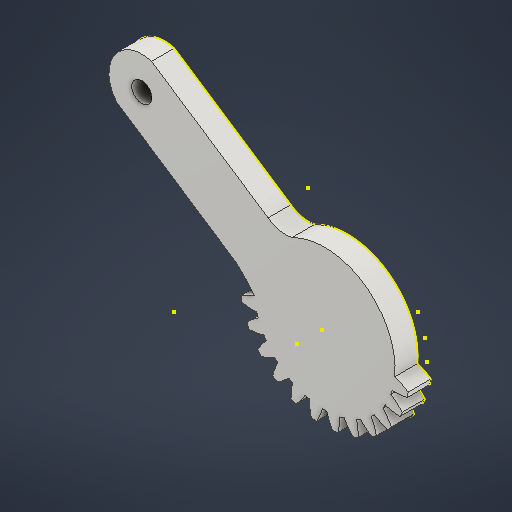
# Autodesk Inventor part: Przekładnia walcowa1
Saved by Autodesk Inventor 2026.1 (Build 301233020, 233B)
## iProperties
CustomPartVersion: 1
Created: 2026-01-25
Part Number: Przekładnia walcowa1
Material: Steel
Document SubType Name: Modeling
Designer: Nitro
Categories: <?xml version="1.0" encoding="UTF-16"?> <MemberInstance><Categories><FamilyTemplate><FamilyTemplateParameter ValueType="xs:double" Id="1" ObjectReferenceKey="da_z" ObjectType="kUserParameterObject"/><FamilyTemplateParameter ValueType="xs:double" Id="2" ObjectReferenceKey="da_b" ObjectType="kUserParameterObject"/><FamilyTemplateParameter ValueType="xs:double" Id="3" ObjectReferenceKey="da_beta" ObjectType="kUserParameterObject"/><FamilyTemplateParameter ValueType="xs:double" Id="4" ObjectReferenceKey="da_da" ObjectType="kUserParameterObject"/><FamilyTemplateParameter ValueType="xs:double" Id="5" ObjectReferenceKey="da_aw" ObjectType="kUserParameterObject"/><FamilyTemplateParameter ValueType="xs:string" Id="6" ObjectReferenceKey="EAIAABAAAACIAQAAAAAAAIAAAAAAAAAA" ObjectType="83910656" SubObjectId="SurfaceGeometry"/></FamilyTemplate><ParamToTemplateMap><ParamToTemplate CategoryParameter="//CategoryParameter[@InternalName='046C89C9-8512-4d59-83FE-43B91F4F132A']" TemplateParameter="1"/><ParamToTemplate CategoryParameter="//CategoryParameter[@InternalName='2552DF32-E462-4b46-AEBF-C6C7768E72AC']" TemplateParameter="2"/><ParamToTemplate CategoryParameter="//CategoryParameter[@InternalName='C9EE641D-15FC-4fae-A226-E94C4372FDD7']" TemplateParameter="3"/><ParamToTemplate><ParamToTemplate CategoryParameter="//CategoryParameter[@InternalName='00B6519A-459B-49c7-AD84-2E56D39A5744']" ConstantValue="0.000000"/></ParamToTemplate><ParamToTemplate><ParamToTemplate CategoryParameter="//CategoryParameter[@InternalName='04B31F0E-C7A6-4894-AA32-9629BEFACF47']" ConstantValue="1.000000"/></ParamToTemplate><ParamToTemplate><ParamToTemplate CategoryParameter="//CategoryParameter[@InternalName='43CBEC2E-7847-49e7-A936-2F7889FCB2D9']" ConstantValue="0.250000"/></ParamToTemplate><ParamToTemplate><ParamToTemplate CategoryParameter="//CategoryParameter[@InternalName='B1EFC894-105D-4ebd-86BF-FA20ED196853']" ConstantValue="0.350000"/></ParamToTemplate><ParamToTemplate><ParamToTemplate CategoryParameter="//CategoryParameter[@InternalName='51175063-3D10-4879-93E8-6246FE8B403D']" ConstantValue="2060000000.000000"/></ParamToTemplate><ParamToTemplate><ParamToTemplate CategoryParameter="//CategoryParameter[@InternalName='A3A52E27-4454-46a9-B0BD-C932399B70AF']" ConstantValue="0.300000"/></ParamToTemplate><ParamToTemplate><ParamToTemplate CategoryParameter="//CategoryParameter[@InternalName='91B76062-C214-41d9-B1B9-14D2AB99603D']" ConstantValue="0.125000"/></ParamToTemplate><ParamToTemplate><ParamToTemplate CategoryParameter="//CategoryParameter[@InternalName='374E806E-8B8A-4dda-A9AA-1039D6500AD2']" ConstantValue="8.000000"/></ParamToTemplate><ParamToTemplate><ParamToTemplate CategoryParameter="//CategoryParameter[@InternalName='2D373A89-B862-43d6-8D0B-0CBF12AB9F6C']" ConstantValue="0.349066"/></ParamToTemplate><ParamToTemplate CategoryParameter="//CategoryParameter[@InternalName='37777632-D6A2-4fac-9D53-DB8ACD95C989']" TemplateParameter="4"/><ParamToTemplate CategoryParameter="//CategoryParameter[@InternalName='FD1017F1-B727-4f7e-9707-0F86F1FF9423']" TemplateParameter="5"/><ParamToTemplate><ParamToTemplate CategoryParameter="//CategoryParameter[@InternalName='9E1B4470-B2D3-4ff1-B813-535BB4CDF51A']" ConstantValue="3520000.000000"/></ParamToTemplate><ParamToTemplate><ParamToTemplate CategoryParameter="//CategoryParameter[@InternalName='F8452263-BFF6-458c-9FB1-07C4B99E95CD']" ConstantValue="11400000.000000"/></ParamToTemplate><ParamToTemplate><ParamToTemplate CategoryParameter="//CategoryParameter[@InternalName='3E3BB259-FD49-497f-8171-6EBC954A3479']" ConstantValue="2.000000"/></ParamToTemplate><ParamToTemplate CategoryParameter="//CategoryParameter[@InternalName='27C3BAF2-7550-4e4b-AE2C-0DB134B7D9B7']" TemplateParameter="6"/></ParamToTemplateMap><Category DisplayName="Gear" InternalName="DC85795E-93AB-48d5-8EEE-5A27447B64BD" Mnemonic="Gear"><CategoryParameter DisplayName="z" InternalName="046C89C9-8512-4d59-83FE-43B91F4F132A" Mnemonic="z"/><CategoryParameter DisplayName="b" InternalName="2552DF32-E462-4b46-AEBF-C6C7768E72AC" Mnemonic="b"/><CategoryParameter DisplayName="||b|" InternalName="C9EE641D-15FC-4fae-A226-E94C4372FDD7" Mnemonic="beta"/><CategoryParameter DisplayName="x" InternalName="00B6519A-459B-49c7-AD84-2E56D39A5744" Mnemonic="x"/><CategoryParameter DisplayName="a*" InternalName="04B31F0E-C7A6-4894-AA32-9629BEFACF47" Mnemonic="a"/><CategoryParameter DisplayName="c*" InternalName="43CBEC2E-7847-49e7-A936-2F7889FCB2D9" Mnemonic="c"/><CategoryParameter DisplayName="r|.f|*" InternalName="B1EFC894-105D-4ebd-86BF-FA20ED196853" Mnemonic="rf"/><CategoryParameter DisplayName="E" InternalName="51175063-3D10-4879-93E8-6246FE8B403D" Mnemonic="E"/><CategoryParameter DisplayName="||m|" InternalName="A3A52E27-4454-46a9-B0BD-C932399B70AF" Mnemonic="mi"/><Category DisplayName="SpurGear" InternalName="26C5A22E-A91E-4dfd-A3B3-23CCAFAE1764" Mnemonic="SpurGear"><CategoryParameter DisplayName="m" InternalName="91B76062-C214-41d9-B1B9-14D2AB99603D" Mnemonic="m"/><CategoryParameter DisplayName="P" InternalName="374E806E-8B8A-4dda-A9AA-1039D6500AD2" Mnemonic="PP"/><CategoryParameter DisplayName="||a|" InternalName="2D373A89-B862-43d6-8D0B-0CBF12AB9F6C" Mnemonic="alpha"/><CategoryParameter DisplayName="d|.a|" InternalName="37777632-D6A2-4fac-9D53-DB8ACD95C989" Mnemonic="da"/><CategoryParameter DisplayName="a|.w|" InternalName="FD1017F1-B727-4f7e-9707-0F86F1FF9423" Mnemonic="aw"/><CategoryParameter DisplayName="||s||.Flim|" InternalName="9E1B4470-B2D3-4ff1-B813-535BB4CDF51A" Mnemonic="sFlim"/><CategoryParameter DisplayName="||s||.Hlim|" InternalName="F8452263-BFF6-458c-9FB1-07C4B99E95CD" Mnemonic="sHlim"/><CategoryParameter DisplayName="typ" InternalName="3E3BB259-FD49-497f-8171-6EBC954A3479" Mnemonic="type"/><CategoryParameter DisplayName="PitchDiameter" InternalName="27C3BAF2-7550-4e4b-AE2C-0DB134B7D9B7" Mnemonic="IDS_PITCHDIAM"/></Category></Category></Categories></MemberInstance>
Density: 1 g/cm^3
Appearance: Steel
d16: 109,375 mm
d17: 0,000 mm
d41: 0,000 mm
d43: 109,375 mm
d46: 109,375 mm
d47: 0,000 mm
d48: 0,000 mm
Author: Nitro
Autodesk Inventor part; units mm, degrees
ref_plane "YZ Plane" through (0, 0, 0) normal (1, 0, 0) x (0, 1, 0)
ref_plane "XZ Plane" through (0, 0, 0) normal (0, 1, 0) x (-1, 0, 0)
ref_plane "XY Plane" through (0, 0, 0) normal (0, 0, 1) x (1, 0, 0)
sketch "Sketch1" plane through (0, 0, 0) normal (0, 0, 1) x (1, 0, 0)
  circle A0 centre (0, 0) radius 16.875
  dimension "d0" = 33.75
  constraints: 1 centre point
  measures "d0" diameter of A0
extrude "Extrusion1" add sketch "Sketch1" along normal blind 10
ref_plane "Work Plane2" through (0, 0, 5) normal (0, 0, 1) x (1, 0, 0)
sketch "Sketch2" plane through (0, 0, 0) normal (0, 0, -1) x (-1, 0, 0)
  circle A0 centre (0, 0) radius 16.875 projected
  circle A1 centre (0, 0) radius 15.625
  dimension "d3" = 31.25
  constraints: 1 centre point, 1 coincident
  measures "d3" diameter of A1
surface extrude "Średnica podziałowa" sketch "Sketch2" against normal through all shown no curves A1
ref_plane "Work Plane8" through (0, 0, 0) normal (0.9921147, 0.1253332, 0) x (0, 0, 1)
ref_plane "Work Plane9" through (0, 0, 0) normal (1, 0, 0) x (0, 1, 0)
spur gear teeth "Przekładnia walcowa" teeth 25 pitch diameter 31.25 tip diameter 33.75 root diameter 28.125 face width 10 start plane through (0, 0, 0) normal (0, 0, -1) x (-1, 0, 0)
sketch "Szkic3" plane through (0, 0, 10) normal (0, 0, 1) x (1, 0, 0)
  point P0 (0, 0)
sketch "Szkic4" plane through (0, 0, 10) normal (0, 0, 1) x (1, 0, 0)
  circle A0 centre (0, 0) radius 14.0625
  circle A1 centre (0, 0) radius 17.845892
  line L0 (-14.033168, -0.907808) -> (-17.792827, -1.375198)
  line L1 (14.055561, -0.907808) -> (17.792827, -1.375198)
  arc A2 (-4.707975, 16.204956) -> (-4.763502, 13.231136) centre (6.715955, 14.50422) ccw
  arc A3 (-4.763502, 13.231136) -> (-5.584892, 12.905924) centre (0, 0) ccw
  arc A4 (-5.584892, 12.905924) -> (-7.66109, 15.035735) centre (-14.824542, 5.975734) ccw
  arc A5 (-7.66109, 15.035735) -> (-8.590074, 14.525022) centre (0, 0) ccw
  arc A6 (-8.590074, 14.525022) -> (-7.904298, 11.630821) centre (2.897908, 15.718734) ccw
  arc A7 (-7.904298, 11.630821) -> (-8.619005, 11.111555) centre (0, 0) ccw
  arc A8 (-8.619005, 11.111555) -> (-11.159638, 12.658124) centre (-15.844907, 2.101281) ccw
  arc A9 (-11.159638, 12.658124) -> (-11.932427, 11.932427) centre (0, 0) ccw
  arc A10 (-11.932427, 11.932427) -> (-10.548437, 9.299698) centre (-1.102225, 15.945581) ccw
  arc A11 (-10.548437, 9.299698) -> (-11.111555, 8.619005) centre (0, 0) ccw
  arc A12 (-11.111555, 8.619005) -> (-13.956985, 9.485157) centre (-15.869677, -1.905202) ccw
  arc A13 (-13.956985, 9.485157) -> (-14.525022, 8.590074) centre (0, 0) ccw
  arc A14 (-14.525022, 8.590074) -> (-12.529779, 6.384241) centre (-5.033101, 15.170509) ccw
  arc A15 (-12.529779, 6.384241) -> (-12.905924, 5.584892) centre (0, 0) ccw
  arc A16 (-12.905924, 5.584892) -> (-15.877363, 5.716202) centre (-14.897298, -5.791975) ccw
  arc A17 (-15.877363, 5.716202) -> (-16.204956, 4.707975) centre (0, 0) ccw
  arc A18 (-16.204956, 4.707975) -> (-13.723829, 3.067639) centre (-8.647729, 13.442218) ccw
  arc A19 (-13.723829, 3.067639) -> (-13.889367, 2.19986) centre (0, 0) ccw
  arc A20 (-13.889367, 2.19986) -> (-16.800108, 1.588078) centre (-12.988866, -9.314817) ccw
  arc A21 (-16.800108, 1.588078) -> (-16.866673, 0.530057) centre (0, 0) ccw
  arc A22 (-16.866673, 0.530057) -> (-14.055561, -0.441714) centre (-11.718989, 10.869303) ccw
  arc A23 (-14.055561, -0.441714) -> (-14.00009, -1.323398) centre (0, 0) ccw
  arc A24 (-14.00009, -1.323398) -> (-16.667241, -2.639832) centre (-10.264296, -12.252374) ccw
  arc A25 (-16.667241, -2.639832) -> (-16.468595, -3.681167) centre (0, 0) ccw
  arc A26 (-16.468595, -3.681167) -> (-13.50413, -3.923312) centre (-14.053901, 7.61343) ccw
  arc A27 (-13.50413, -3.923312) -> (-13.231136, -4.763502) centre (0, 0) ccw
  arc A28 (-13.231136, -4.763502) -> (-15.487109, -6.701871) centre (-6.894783, -14.42007) ccw
  arc A29 (-15.487109, -6.701871) -> (-15.035735, -7.66109) centre (0, 0) ccw
  arc A30 (-15.035735, -7.66109) -> (-12.104185, -7.158395) centre (-15.505755, 3.879177) ccw
  arc A31 (-12.104185, -7.158395) -> (-11.630821, -7.904298) centre (0, 0) ccw
  arc A32 (-11.630821, -7.904298) -> (-13.333866, -10.342807) centre (-3.092045, -15.6817) ccw
  arc A33 (-13.333866, -10.342807) -> (-12.658124, -11.159638) centre (0, 0) ccw
  arc A34 (-12.658124, -11.159638) -> (-9.943689, -9.943689) centre (-15.983325, -0.098819) ccw
  arc A35 (-9.943689, -9.943689) -> (-9.299698, -10.548437) centre (0, 0) ccw
  arc A36 (-9.299698, -10.548437) -> (-10.342807, -13.333866) centre (0.904978, -15.957991) ccw
  arc A37 (-10.342807, -13.333866) -> (-9.485157, -13.956985) centre (0, 0) ccw
  arc A38 (-9.485157, -13.956985) -> (-7.158395, -12.104185) centre (-15.456605, -4.070606) ccw
  arc A39 (-7.158395, -12.104185) -> (-6.384241, -12.529779) centre (0, 0) ccw
  arc A40 (-6.384241, -12.529779) -> (-6.701871, -15.487109) centre (4.845137, -15.231582) ccw
  arc A41 (-6.701871, -15.487109) -> (-5.716202, -15.877363) centre (0, 0) ccw
  arc A42 (-5.716202, -15.877363) -> (-3.923312, -13.50413) centre (-13.958688, -7.786621) ccw
  arc A43 (-3.923312, -13.50413) -> (-3.067639, -13.723829) centre (0, 0) ccw
  arc A44 (-3.067639, -13.723829) -> (-2.639832, -16.667241) centre (8.480859, -13.548118) ccw
  arc A45 (-2.639832, -16.667241) -> (-1.588078, -16.800108) centre (0, 0) ccw
  arc A46 (-1.588078, -16.800108) -> (-0.441714, -14.055561) centre (-11.583697, -11.013375) ccw
  arc A47 (-0.441714, -14.055561) -> (0.441714, -14.055561) centre (0, 0) ccw
  arc A48 (0.441714, -14.055561) -> (1.588078, -16.800108) centre (11.583697, -11.013375) ccw
  arc A49 (1.588078, -16.800108) -> (2.639832, -16.667241) centre (0, 0) ccw
  arc A50 (2.639832, -16.667241) -> (3.067639, -13.723829) centre (-8.480859, -13.548118) ccw
  arc A51 (3.067639, -13.723829) -> (3.923312, -13.50413) centre (0, 0) ccw
  arc A52 (3.923312, -13.50413) -> (5.716202, -15.877363) centre (13.958688, -7.786621) ccw
  arc A53 (5.716202, -15.877363) -> (6.701871, -15.487109) centre (0, 0) ccw
  arc A54 (6.701871, -15.487109) -> (6.384241, -12.529779) centre (-4.845137, -15.231582) ccw
  arc A55 (6.384241, -12.529779) -> (7.158395, -12.104185) centre (0, 0) ccw
  arc A56 (7.158395, -12.104185) -> (9.485157, -13.956985) centre (15.456605, -4.070606) ccw
  arc A57 (9.485157, -13.956985) -> (10.342807, -13.333866) centre (0, 0) ccw
  arc A58 (10.342807, -13.333866) -> (9.299698, -10.548437) centre (-0.904978, -15.957991) ccw
  arc A59 (9.299698, -10.548437) -> (9.943689, -9.943689) centre (0, 0) ccw
  arc A60 (9.943689, -9.943689) -> (12.658124, -11.159638) centre (15.983325, -0.098819) ccw
  arc A61 (12.658124, -11.159638) -> (13.333866, -10.342807) centre (0, 0) ccw
  arc A62 (13.333866, -10.342807) -> (11.630821, -7.904298) centre (3.092045, -15.6817) ccw
  arc A63 (11.630821, -7.904298) -> (12.104185, -7.158395) centre (0, 0) ccw
  arc A64 (12.104185, -7.158395) -> (15.035735, -7.66109) centre (15.505755, 3.879177) ccw
  arc A65 (15.035735, -7.66109) -> (15.487109, -6.701871) centre (0, 0) ccw
  arc A66 (15.487109, -6.701871) -> (13.231136, -4.763502) centre (6.894783, -14.42007) ccw
  arc A67 (13.231136, -4.763502) -> (13.50413, -3.923312) centre (0, 0) ccw
  arc A68 (13.50413, -3.923312) -> (16.468595, -3.681167) centre (14.053901, 7.61343) ccw
  arc A69 (16.468595, -3.681167) -> (16.667241, -2.639832) centre (0, 0) ccw
  arc A70 (16.667241, -2.639832) -> (14.00009, -1.323398) centre (10.264296, -12.252374) ccw
  arc A71 (14.00009, -1.323398) -> (14.055561, -0.441714) centre (0, 0) ccw
  arc A72 (14.055561, -0.441714) -> (16.866673, 0.530057) centre (11.718989, 10.869303) ccw
  arc A73 (16.866673, 0.530057) -> (16.800108, 1.588078) centre (0, 0) ccw
  arc A74 (16.800108, 1.588078) -> (13.889367, 2.19986) centre (12.988866, -9.314817) ccw
  arc A75 (13.889367, 2.19986) -> (13.723829, 3.067639) centre (0, 0) ccw
  arc A76 (13.723829, 3.067639) -> (16.204956, 4.707975) centre (8.647729, 13.442218) ccw
  arc A77 (16.204956, 4.707975) -> (15.877363, 5.716202) centre (0, 0) ccw
  arc A78 (15.877363, 5.716202) -> (12.905924, 5.584892) centre (14.897298, -5.791975) ccw
  arc A79 (12.905924, 5.584892) -> (12.529779, 6.384241) centre (0, 0) ccw
  arc A80 (12.529779, 6.384241) -> (14.525022, 8.590074) centre (5.033101, 15.170509) ccw
  arc A81 (14.525022, 8.590074) -> (13.956985, 9.485157) centre (0, 0) ccw
  arc A82 (13.956985, 9.485157) -> (11.111555, 8.619005) centre (15.869677, -1.905202) ccw
  arc A83 (11.111555, 8.619005) -> (10.548437, 9.299698) centre (0, 0) ccw
  arc A84 (10.548437, 9.299698) -> (11.932427, 11.932427) centre (1.102225, 15.945581) ccw
  arc A85 (11.932427, 11.932427) -> (11.159638, 12.658124) centre (0, 0) ccw
  arc A86 (11.159638, 12.658124) -> (8.619005, 11.111555) centre (15.844907, 2.101281) ccw
  arc A87 (8.619005, 11.111555) -> (7.904298, 11.630821) centre (0, 0) ccw
  arc A88 (7.904298, 11.630821) -> (8.590074, 14.525022) centre (-2.897908, 15.718734) ccw
  arc A89 (8.590074, 14.525022) -> (7.66109, 15.035735) centre (0, 0) ccw
  arc A90 (7.66109, 15.035735) -> (5.584892, 12.905924) centre (14.824542, 5.975734) ccw
  arc A91 (5.584892, 12.905924) -> (4.763502, 13.231136) centre (0, 0) ccw
  arc A92 (4.763502, 13.231136) -> (4.707975, 16.204956) centre (-6.715955, 14.50422) ccw
  arc A93 (4.707975, 16.204956) -> (3.681167, 16.468595) centre (0, 0) ccw
  arc A94 (3.681167, 16.468595) -> (2.19986, 13.889367) centre (12.872698, 9.474709) ccw
  arc A95 (2.19986, 13.889367) -> (1.323398, 14.00009) centre (0, 0) ccw
  arc A96 (1.323398, 14.00009) -> (0.530057, 16.866673) centre (-10.112014, 12.378353) ccw
  arc A97 (0.530057, 16.866673) -> (-0.530057, 16.866673) centre (0, 0) ccw
  arc A98 (-0.530057, 16.866673) -> (-1.323398, 14.00009) centre (10.112014, 12.378353) ccw
  arc A99 (-1.323398, 14.00009) -> (-2.19986, 13.889367) centre (0, 0) ccw
  arc A100 (-2.19986, 13.889367) -> (-3.681167, 16.468595) centre (-12.872698, 9.474709) ccw
  arc A101 (-3.681167, 16.468595) -> (-4.707975, 16.204956) centre (0, 0) ccw
  point P0 (14.00009, -1.323398)
  point P1 (13.50413, -3.923312)
  point P2 (13.231136, -4.763502)
  point P3 (12.104185, -7.158395)
  point P4 (11.630821, -7.904298)
  point P5 (9.943689, -9.943689)
  point P6 (9.299698, -10.548437)
  point P7 (7.158395, -12.104185)
  point P8 (6.384241, -12.529779)
  point P9 (3.923312, -13.50413)
  point P10 (3.067639, -13.723829)
  point P11 (0.441714, -14.055561)
  point P12 (-0.441714, -14.055561)
  point P13 (-3.067639, -13.723829)
  point P14 (-3.923312, -13.50413)
  point P15 (-6.384241, -12.529779)
  point P16 (-7.158395, -12.104185)
  point P17 (-9.299698, -10.548437)
  point P18 (-9.943689, -9.943689)
  point P19 (-11.630821, -7.904298)
  point P20 (-12.104185, -7.158395)
  point P21 (-13.231136, -4.763502)
  point P22 (-13.50413, -3.923312)
  point P23 (-14.00009, -1.323398)
  constraints: 4 end point, 2 coincident, 2 point on circle, 1 centre point, 4 other
extrude "Wyciągnięcie proste2" cut sketch "Szkic4" against normal blind 10 contours A0 A74 A73 A72 | A0 A78 A77 A76 | A0 A82 A81 A80 | A0 A86 A85 A84 | A0 A90 A89 A88 | A0 A94 A93 A92 | A0 A98 A97 A96 | A0 A2 A101 A100 | A0 A6 A5 A4 | A0 A10 A9 A8 | A0 A14 A13 A12 | A0 A18 A17 A16 | A0 A22 A21 A20 | A1
sketch "Szkic5" plane through (0, 0, 10) normal (0, 0, 1) x (1, 0, 0)
  circle A0 centre (0, 0) radius 25.288226
  constraints: 1 centre point, 1 coincident
extrude "Wyciągnięcie proste3" cut sketch "Szkic5" against normal blind 5
sketch "Szkic6" plane through (0, 0, 5) normal (0, 0, 1) x (1, 0, 0)
  point P0 (0, 0)
sketch "Szkic7" plane through (0, 0, 5) normal (0, 0, 1) x (1, 0, 0)
  point P0 (0, 0)
sketch "Szkic8" plane through (0, 0, 5) normal (0, 0, 1) x (1, 0, 0)
  arc A0 (13.231136, -4.763502) -> (13.50413, -3.923312) centre (0, 0) ccw
  arc A1 (13.50413, -3.923312) -> (16.468595, -3.681167) centre (14.053901, 7.61343) ccw
  arc A2 (16.468595, -3.681167) -> (16.667241, -2.639832) centre (0, 0) ccw
  arc A3 (16.667241, -2.639832) -> (14.00009, -1.323398) centre (10.264296, -12.252374) ccw
  arc A4 (14.00009, -1.323398) -> (-14.00009, -1.323398) centre (0, 0) ccw
  arc A5 (-14.00009, -1.323398) -> (-16.667241, -2.639832) centre (-10.264296, -12.252374) ccw
  arc A6 (-16.667241, -2.639832) -> (-16.468595, -3.681167) centre (0, 0) ccw
  arc A7 (-16.468595, -3.681167) -> (-13.50413, -3.923312) centre (-14.053901, 7.61343) ccw
  arc A8 (-13.50413, -3.923312) -> (-13.231136, -4.763502) centre (0, 0) ccw
  arc A9 (-13.231136, -4.763502) -> (-15.487109, -6.701871) centre (-6.894783, -14.42007) ccw
  arc A10 (-15.487109, -6.701871) -> (-15.035735, -7.66109) centre (0, 0) ccw
  arc A11 (-15.035735, -7.66109) -> (-12.104185, -7.158395) centre (-15.505755, 3.879177) ccw
  arc A12 (-12.104185, -7.158395) -> (-11.630821, -7.904298) centre (0, 0) ccw
  arc A13 (-11.630821, -7.904298) -> (-13.333866, -10.342807) centre (-3.092045, -15.6817) ccw
  arc A14 (-13.333866, -10.342807) -> (-12.658124, -11.159638) centre (0, 0) ccw
  arc A15 (-12.658124, -11.159638) -> (-9.943689, -9.943689) centre (-15.983325, -0.098819) ccw
  arc A16 (-9.943689, -9.943689) -> (-9.299698, -10.548437) centre (0, 0) ccw
  arc A17 (-9.299698, -10.548437) -> (-10.342807, -13.333866) centre (0.904978, -15.957991) ccw
  arc A18 (-10.342807, -13.333866) -> (-9.485157, -13.956985) centre (0, 0) ccw
  arc A19 (-9.485157, -13.956985) -> (-7.158395, -12.104185) centre (-15.456605, -4.070606) ccw
  arc A20 (-7.158395, -12.104185) -> (-6.384241, -12.529779) centre (0, 0) ccw
  arc A21 (-6.384241, -12.529779) -> (-6.701871, -15.487109) centre (4.845137, -15.231582) ccw
  arc A22 (-6.701871, -15.487109) -> (-5.716202, -15.877363) centre (0, 0) ccw
  arc A23 (-5.716202, -15.877363) -> (-3.923312, -13.50413) centre (-13.958688, -7.786621) ccw
  arc A24 (-3.923312, -13.50413) -> (-3.067639, -13.723829) centre (0, 0) ccw
  arc A25 (-3.067639, -13.723829) -> (-2.639832, -16.667241) centre (8.480859, -13.548118) ccw
  arc A26 (-2.639832, -16.667241) -> (-1.588078, -16.800108) centre (0, 0) ccw
  arc A27 (-1.588078, -16.800108) -> (-0.441714, -14.055561) centre (-11.583697, -11.013375) ccw
  arc A28 (-0.441714, -14.055561) -> (0.441714, -14.055561) centre (0, 0) ccw
  arc A29 (0.441714, -14.055561) -> (1.588078, -16.800108) centre (11.583697, -11.013375) ccw
  arc A30 (1.588078, -16.800108) -> (2.639832, -16.667241) centre (0, 0) ccw
  arc A31 (2.639832, -16.667241) -> (3.067639, -13.723829) centre (-8.480859, -13.548118) ccw
  arc A32 (3.067639, -13.723829) -> (3.923312, -13.50413) centre (0, 0) ccw
  arc A33 (3.923312, -13.50413) -> (5.716202, -15.877363) centre (13.958688, -7.786621) ccw
  arc A34 (5.716202, -15.877363) -> (6.701871, -15.487109) centre (0, 0) ccw
  arc A35 (6.701871, -15.487109) -> (6.384241, -12.529779) centre (-4.845137, -15.231582) ccw
  arc A36 (6.384241, -12.529779) -> (7.158395, -12.104185) centre (0, 0) ccw
  arc A37 (7.158395, -12.104185) -> (9.485157, -13.956985) centre (15.456605, -4.070606) ccw
  arc A38 (9.485157, -13.956985) -> (10.342807, -13.333866) centre (0, 0) ccw
  arc A39 (10.342807, -13.333866) -> (9.299698, -10.548437) centre (-0.904978, -15.957991) ccw
  arc A40 (9.299698, -10.548437) -> (9.943689, -9.943689) centre (0, 0) ccw
  arc A41 (9.943689, -9.943689) -> (12.658124, -11.159638) centre (15.983325, -0.098819) ccw
  arc A42 (12.658124, -11.159638) -> (13.333866, -10.342807) centre (0, 0) ccw
  arc A43 (13.333866, -10.342807) -> (11.630821, -7.904298) centre (3.092045, -15.6817) ccw
  arc A44 (11.630821, -7.904298) -> (12.104185, -7.158395) centre (0, 0) ccw
  arc A45 (12.104185, -7.158395) -> (15.035735, -7.66109) centre (15.505755, 3.879177) ccw
  arc A46 (15.035735, -7.66109) -> (15.487109, -6.701871) centre (0, 0) ccw
  arc A47 (15.487109, -6.701871) -> (13.231136, -4.763502) centre (6.894783, -14.42007) ccw
  line L0 (-8.172118, 11.44423) -> (-34.515152, 28.894503)
  line L1 (-14.060739, 0.222517) -> (-41.477523, 18.384068)
  line L2 (-5.892742, 15.787946) -> (-5.893343, 15.7868)
  arc A48 (-34.515152, 28.894503) -> (-41.477523, 18.384068) centre (-36.452078, 22.61633) ccw
  arc A49 (-11.261601, 13.49078) -> (-6.506127, 12.466925) centre (-7.785272, 18.081458) ccw
  line L3 (-10.656444, 13.089909) -> (-17.618815, 2.579474)
  arc A50 (14.00009, -1.323398) -> (-14.00009, -1.323398) centre (0, 0) ccw
  arc A51 (-14.00009, -1.323398) -> (-17.618815, 2.579474) centre (-34.4614, -16.665962) ccw
  constraints: 11 point on circle, 8 end point, 4 point on line, 3 centre point, 2 coincident, 1 parallel, 1 perpendicular
extrude "Wyciągnięcie proste4" add sketch "Szkic8" against normal blind 5 contours A4 L0 A49 | A4 L1 L3 L0 | L3 L1 A48 L0 A49 | A4 A51 L1
sketch "Szkic9" plane through (0, 0, 5) normal (0, 0, 1) x (1, 0, 0)
  arc A0 (13.231136, -4.763502) -> (13.50413, -3.923312) centre (0, 0) ccw
  arc A1 (13.50413, -3.923312) -> (16.468595, -3.681167) centre (14.053901, 7.61343) ccw
  arc A2 (16.468595, -3.681167) -> (16.667241, -2.639832) centre (0, 0) ccw
  arc A3 (16.667241, -2.639832) -> (14.00009, -1.323398) centre (10.264296, -12.252374) ccw
  arc A4 (14.00009, -1.323398) -> (-6.506127, 12.466925) centre (0, 0) ccw
  arc A5 (-11.261601, 13.49078) -> (-6.506127, 12.466925) centre (-7.785272, 18.081458) ccw
  line L0 (-11.261601, 13.49078) -> (-34.515152, 28.894503)
  arc A6 (-34.515152, 28.894503) -> (-41.477523, 18.384068) centre (-36.452078, 22.61633) ccw
  line L1 (-41.477523, 18.384068) -> (-17.618815, 2.579474)
  arc A7 (-14.00009, -1.323398) -> (-17.618815, 2.579474) centre (-34.4614, -16.665962) ccw
  arc A8 (-14.00009, -1.323398) -> (-16.667241, -2.639832) centre (-10.264296, -12.252374) ccw
  arc A9 (-16.667241, -2.639832) -> (-16.468595, -3.681167) centre (0, 0) ccw
  arc A10 (-16.468595, -3.681167) -> (-13.50413, -3.923312) centre (-14.053901, 7.61343) ccw
  arc A11 (-13.50413, -3.923312) -> (-13.231136, -4.763502) centre (0, 0) ccw
  arc A12 (-13.231136, -4.763502) -> (-15.487109, -6.701871) centre (-6.894783, -14.42007) ccw
  arc A13 (-15.487109, -6.701871) -> (-15.035735, -7.66109) centre (0, 0) ccw
  arc A14 (-15.035735, -7.66109) -> (-12.104185, -7.158395) centre (-15.505755, 3.879177) ccw
  arc A15 (-12.104185, -7.158395) -> (-11.630821, -7.904298) centre (0, 0) ccw
  arc A16 (-11.630821, -7.904298) -> (-13.333866, -10.342807) centre (-3.092045, -15.6817) ccw
  arc A17 (-13.333866, -10.342807) -> (-12.658124, -11.159638) centre (0, 0) ccw
  arc A18 (-12.658124, -11.159638) -> (-9.943689, -9.943689) centre (-15.983325, -0.098819) ccw
  arc A19 (-9.943689, -9.943689) -> (-9.299698, -10.548437) centre (0, 0) ccw
  arc A20 (-9.299698, -10.548437) -> (-10.342807, -13.333866) centre (0.904978, -15.957991) ccw
  arc A21 (-10.342807, -13.333866) -> (-9.485157, -13.956985) centre (0, 0) ccw
  arc A22 (-9.485157, -13.956985) -> (-7.158395, -12.104185) centre (-15.456605, -4.070606) ccw
  arc A23 (-7.158395, -12.104185) -> (-6.384241, -12.529779) centre (0, 0) ccw
  arc A24 (-6.384241, -12.529779) -> (-6.701871, -15.487109) centre (4.845137, -15.231582) ccw
  arc A25 (-6.701871, -15.487109) -> (-5.716202, -15.877363) centre (0, 0) ccw
  arc A26 (-5.716202, -15.877363) -> (-3.923312, -13.50413) centre (-13.958688, -7.786621) ccw
  arc A27 (-3.923312, -13.50413) -> (-3.067639, -13.723829) centre (0, 0) ccw
  arc A28 (-3.067639, -13.723829) -> (-2.639832, -16.667241) centre (8.480859, -13.548118) ccw
  arc A29 (-2.639832, -16.667241) -> (-1.588078, -16.800108) centre (0, 0) ccw
  arc A30 (-1.588078, -16.800108) -> (-0.441714, -14.055561) centre (-11.583697, -11.013375) ccw
  arc A31 (-0.441714, -14.055561) -> (0.441714, -14.055561) centre (0, 0) ccw
  arc A32 (0.441714, -14.055561) -> (1.588078, -16.800108) centre (11.583697, -11.013375) ccw
  arc A33 (1.588078, -16.800108) -> (2.639832, -16.667241) centre (0, 0) ccw
  arc A34 (2.639832, -16.667241) -> (3.067639, -13.723829) centre (-8.480859, -13.548118) ccw
  arc A35 (3.067639, -13.723829) -> (3.923312, -13.50413) centre (0, 0) ccw
  arc A36 (3.923312, -13.50413) -> (5.716202, -15.877363) centre (13.958688, -7.786621) ccw
  arc A37 (5.716202, -15.877363) -> (6.701871, -15.487109) centre (0, 0) ccw
  arc A38 (6.701871, -15.487109) -> (6.384241, -12.529779) centre (-4.845137, -15.231582) ccw
  arc A39 (6.384241, -12.529779) -> (7.158395, -12.104185) centre (0, 0) ccw
  arc A40 (7.158395, -12.104185) -> (9.485157, -13.956985) centre (15.456605, -4.070606) ccw
  arc A41 (9.485157, -13.956985) -> (10.342807, -13.333866) centre (0, 0) ccw
  arc A42 (10.342807, -13.333866) -> (9.299698, -10.548437) centre (-0.904978, -15.957991) ccw
  arc A43 (9.299698, -10.548437) -> (9.943689, -9.943689) centre (0, 0) ccw
  arc A44 (9.943689, -9.943689) -> (12.658124, -11.159638) centre (15.983325, -0.098819) ccw
  arc A45 (12.658124, -11.159638) -> (13.333866, -10.342807) centre (0, 0) ccw
  arc A46 (13.333866, -10.342807) -> (11.630821, -7.904298) centre (3.092045, -15.6817) ccw
  arc A47 (11.630821, -7.904298) -> (12.104185, -7.158395) centre (0, 0) ccw
  arc A48 (12.104185, -7.158395) -> (15.035735, -7.66109) centre (15.505755, 3.879177) ccw
  arc A49 (15.035735, -7.66109) -> (15.487109, -6.701871) centre (0, 0) ccw
  arc A50 (15.487109, -6.701871) -> (13.231136, -4.763502) centre (6.894783, -14.42007) ccw
  circle A51 centre (-36.452078, 22.61633) radius 3
  dimension "d55" = 6
  constraints: 1 centre point, 1 coincident
  measures "d55" diameter of A51
extrude "Wyciągnięcie proste5" cut sketch "Szkic9" against normal blind 5 contours A51
sketch "Szkic10" plane through (0, 0, 0) normal (0, 0, -1) x (-1, 0, 0)
  circle A0 centre (0, 0) radius 3
  dimension "d58" = 6
  constraints: 1 centre point, 1 coincident
  measures "d58" diameter of A0
extrude "Wyciągnięcie proste6" cut sketch "Szkic10" against normal blind 5
sketch "Szkic11" plane through (0, 0, 5) normal (0, 0, 1) x (1, 0, 0)
  circle A0 centre (0, 0) radius 3.383346
  constraints: 1 centre point, 1 coincident
extrude "Wyciągnięcie proste7" add sketch "Szkic11" against normal blind 5
sketch "Szkic12" plane through (0, 0, 5) normal (0, 0, 1) x (1, 0, 0)
  line L0 (-14.975228, 8.393911) -> (3.365709, -3.755576) construction
  line L1 (-16.9081, 5.476035) -> (1.432836, -6.673452)
  line L2 (5.298582, -0.837699) -> (-13.042355, 11.311788)
  arc A0 (-13.042355, 11.311788) -> (-16.9081, 5.476035) centre (-14.975228, 8.393911) ccw
  arc A1 (1.432836, -6.673452) -> (5.298582, -0.837699) centre (3.365709, -3.755576) ccw
  line L3 (-41.477523, 18.384068) -> (-17.618815, 2.579474)
  line L4 (-11.261601, 13.49078) -> (-34.515152, 28.894503)
  point P0 (0, 0)
  point P1 (-5.804759, 2.319168)
  dimension "d63" = 11
  dimension "d64" = 7
  dimension "d65" = 6.3
  dimension "d66" = 6.30729
  dimension "d67" = 3.5
  dimension "d68" = 14.97523
  constraints: 8 end point, 4 point on circle, 4 tangent, 3 parallel, 2 centre point, 1 midpoint
  measures "d63" distance of point (-5.805, 2.319) L0.end
  measures "d64" diameter of A1
  measures "d65" distance between parallel lines of L0 L4
  measures "d66" distance between parallel lines of L3 L0
  measures "d67" radius of A0
  measures "d68" horizontal distance of point (0, 0) L0.start
extrude "Wyciągnięcie proste8" cut sketch "Szkic12" against normal blind 3
sketch "Szkic13" plane through (0, 0, 5) normal (0, 0, 1) x (1, 0, 0)
  point P0 (0, 0)
sketch "Szkic14" plane through (0, 0, 2) normal (0, 0, 1) x (1, 0, 0)
  arc A0 (1.432836, -6.673452) -> (5.298582, -0.837699) centre (3.365709, -3.755576) ccw
  line L0 (-13.042355, 11.311788) -> (5.298582, -0.837699)
  arc A1 (-13.042355, 11.311788) -> (-16.9081, 5.476035) centre (-14.975228, 8.393911) ccw
  line L1 (1.432836, -6.673452) -> (-16.9081, 5.476035)
  line L2 (-17.893104, 10.326784) -> (6.283586, -5.688449) construction
  line L3 (-16.936243, 5.614628) -> (1.571429, -6.645309)
  line L4 (5.326725, -0.976292) -> (-13.180947, 11.283645)
  arc A2 (-13.180947, 11.283645) -> (-16.936243, 5.614628) centre (-15.058595, 8.449136) ccw
  arc A3 (1.571429, -6.645309) -> (5.326725, -0.976292) centre (3.449077, -3.810801) ccw
  point P0 (0, 0)
  point P1 (-5.804759, 2.319168)
  point P2 (6.283586, -5.688449)
  point P3 (-17.893104, 10.326784)
  dimension "d71" = 6.8
  constraints: 8 end point, 8 point on circle, 4 tangent, 2 centre point, 2 point on line, 1 midpoint, 1 parallel
  measures "d71" diameter of A3
extrude "Wyciągnięcie proste9" add sketch "Szkic14" along normal blind 3 contours L1 A1 A2 L3 A3 A0 | A3 L4 A2 A1 L0 A0
sketch "Szkic15" plane through (0, 0, 2) normal (0, 0, 1) x (1, 0, 0)
  point P0 (0, 0)
sketch "Szkic16" plane through (0, 0, 2) normal (0, 0, 1) x (1, 0, 0)
  arc A0 (1.571429, -6.645309) -> (5.326725, -0.976292) centre (3.449077, -3.810801) ccw
  line L0 (5.326725, -0.976292) -> (-13.180947, 11.283645)
  arc A1 (-13.180947, 11.283645) -> (-16.936243, 5.614628) centre (-15.058595, 8.449136) ccw
  line L1 (-16.936243, 5.614628) -> (1.571429, -6.645309)
  line L2 (-15.058595, 8.449136) -> (3.449077, -3.810801)
  line L3 (-17.476264, 10.05066) -> (5.866746, -5.412324)
  line L4 (4.762247, -7.079682) -> (6.971245, -3.744966)
  line L5 (-3.927111, 5.153676) -> (-7.682407, -0.515341)
  line L6 (-3.927111, 5.153676) -> (6.971245, -3.744966)
  line L7 (4.762247, -7.079682) -> (-7.682407, -0.515341)
  line L8 (-16.371766, 11.718017) -> (-18.580763, 8.383302)
  line L9 (-3.927111, 5.153676) -> (-16.371766, 11.718017)
  line L10 (-18.580763, 8.383302) -> (-7.682407, -0.515341)
  point P0 (0, 0)
  point P1 (-5.804759, 2.319168)
  point P2 (-5.804759, 2.319168)
  point P3 (-18.454392, 8.280118)
  point P4 (4.617946, -7.003565)
  point P5 (-16.227464, 11.641901)
  point P6 (6.844874, -3.641782)
  dimension "d74" = 4
  dimension "d75" = 4
  dimension "d76" = 28
  constraints: 18 end point, 7 midpoint, 3 perpendicular, 2 coincident, 1 point on line
  measures "d74" distance of L4.start L4.end
  measures "d75" distance of L8.start L8.end
  measures "d76" distance from line of L8 point (5.867, -5.412)
extrude "Wyciągnięcie proste10" add sketch "Szkic16" along normal blind 3 contours L1 L7 A0 | L1 A1 L10 | L9 A1 L0 | L0 A0 L6
sketch "Szkic17" plane through (0, 0, 5) normal (0, 0, 1) x (1, 0, 0)
  circle A0 centre (-36.452078, 22.61633) radius 3
  circle A1 centre (-36.452078, 22.61633) radius 2
  point P0 (0, 0)
  dimension "d79" = 4
  constraints: 1 centre point, 1 coincident
  measures "d79" diameter of A1
extrude "Wyciągnięcie proste11" add sketch "Szkic17" against normal blind 5
sketch "Szkic18" plane through (0, 0, 5) normal (0, 0, 1) x (1, 0, 0)
  circle A0 centre (-11.788501, 5.153676) radius 43.328523
  point P0 (0, 0)
  constraints: 1 centre point
extrude "Wyciągnięcie proste12" cut sketch "Szkic18" against normal blind 0.5
sketch "Szkic19" plane through (0, 0, 2) normal (0, 0, 1) x (1, 0, 0)
  line L0 (-18.454392, 8.280118) -> (-7.682407, -0.515341)
  line L1 (-7.682407, -0.515341) -> (4.617946, -7.003565)
  arc A0 (4.617946, -7.003565) -> (6.844874, -3.641782) centre (3.449077, -3.810801) ccw
  line L2 (6.844874, -3.641782) -> (-3.927111, 5.153676)
  line L3 (-3.927111, 5.153676) -> (-16.227464, 11.641901)
  arc A1 (-16.227464, 11.641901) -> (-18.454392, 8.280118) centre (-15.058595, 8.449136) ccw
  point P0 (0, 0)
extrude "Wyciągnięcie proste13" cut sketch "Szkic19" against normal blind 0.5
sketch "Szkic20" plane through (0, 0, 1.5) normal (0, 0, 1) x (1, 0, 0)
  line L0 (4.617946, -7.003565) -> (-7.682407, -0.515341)
  arc A0 (4.617946, -7.003565) -> (6.844874, -3.641782) centre (3.449077, -3.810801) ccw
  line L1 (-3.927111, 5.153676) -> (6.844874, -3.641782)
  line L2 (-16.227464, 11.641901) -> (-3.927111, 5.153676)
  arc A1 (-16.227464, 11.641901) -> (-18.454392, 8.280118) centre (-15.058595, 8.449136) ccw
  line L3 (-7.682407, -0.515341) -> (-18.454392, 8.280118)
  point P0 (0, 0)
extrude "Wyciągnięcie proste14" cut sketch "Szkic20" against normal blind 10
sketch "Szkic21" plane through (0, 0, 4.5) normal (0, 0, 1) x (1, 0, 0)
  line L0 (-21.385351, 7.172522) -> (-15.898537, 14.774733)
  line L1 (-15.898537, 14.774733) -> (9.517885, -3.569292)
  line L2 (9.517885, -3.569292) -> (4.031072, -11.171504)
  line L3 (4.031072, -11.171504) -> (-21.385351, 7.172522)
  point P0 (0, 0)
  constraints: 8 end point, 2 parallel, 1 perpendicular
extrude "Wyciągnięcie proste15" add sketch "Szkic21" against normal blind 2
sketch "Szkic22" plane through (0, 0, 2.5) normal (0, 0, -1) x (-1, 0, 0)
  line L0 (7.682407, -0.515341) -> (-4.617946, -7.003565)
  line L1 (18.454392, 8.280118) -> (7.682407, -0.515341)
  arc A0 (18.454392, 8.280118) -> (16.227464, 11.641901) centre (15.058595, 8.449136) ccw
  line L2 (3.927111, 5.153676) -> (16.227464, 11.641901)
  line L3 (-6.844874, -3.641782) -> (3.927111, 5.153676)
  arc A1 (-6.844874, -3.641782) -> (-4.617946, -7.003565) centre (-3.449077, -3.810801) ccw
  point P0 (0, 0)
extrude "Wyciągnięcie proste16" cut sketch "Szkic22" against normal blind 0.5
sketch "Szkic23" plane through (0, 0, 0) normal (0, 0, -1) x (-1, 0, 0)
  line L0 (3.927111, 5.153676) -> (16.227464, 11.641901)
  line L1 (-6.844874, -3.641782) -> (3.927111, 5.153676)
  arc A0 (-6.844874, -3.641782) -> (-4.617946, -7.003565) centre (-3.449077, -3.810801) ccw
  line L2 (7.682407, -0.515341) -> (-4.617946, -7.003565)
  line L3 (18.454392, 8.280118) -> (7.682407, -0.515341)
  arc A1 (18.454392, 8.280118) -> (16.227464, 11.641901) centre (15.058595, 8.449136) ccw
  point P0 (0, 0)
sketch "Szkic24" plane through (0, 0, 0) normal (0, 0, -1) x (-1, 0, 0)
  point P0 (0, 0)
sketch "Szkic25" plane through (0, 0, 3) normal (0, 0, -1) x (-1, 0, 0)
  line L0 (3.927111, 5.153676) -> (16.227464, 11.641901)
  line L1 (-6.844874, -3.641782) -> (3.927111, 5.153676)
  arc A0 (-6.844874, -3.641782) -> (-4.617946, -7.003565) centre (-3.449077, -3.810801) ccw
  line L2 (7.682407, -0.515341) -> (-4.617946, -7.003565)
  line L3 (18.454392, 8.280118) -> (7.682407, -0.515341)
  arc A1 (18.454392, 8.280118) -> (16.227464, 11.641901) centre (15.058595, 8.449136) ccw
  point P0 (0, 0)
extrude "Wyciągnięcie proste17" add sketch "Szkic25" along normal blind 3
sketch "Szkic26" plane through (0, 0, 0) normal (0, 0, -1) x (-1, 0, 0)
  line L0 (7.682407, -0.515341) -> (-4.617946, -7.003565)
  arc A0 (-6.844874, -3.641782) -> (-4.617946, -7.003565) centre (-3.449077, -3.810801) ccw
  line L1 (-6.844874, -3.641782) -> (3.927111, 5.153676)
  circle A1 centre (36.452078, 22.61633) radius 2
  arc A2 (6.506127, 12.466925) -> (-14.00009, -1.323398) centre (0, 0) ccw
  arc A3 (-14.00009, -1.323398) -> (-16.667241, -2.639832) centre (-10.264296, -12.252374) ccw
  arc A4 (-16.667241, -2.639832) -> (-16.468595, -3.681167) centre (0, 0) ccw
  arc A5 (-16.468595, -3.681167) -> (-13.50413, -3.923312) centre (-14.053901, 7.61343) ccw
  arc A6 (-13.50413, -3.923312) -> (-13.231136, -4.763502) centre (0, 0) ccw
  arc A7 (-13.231136, -4.763502) -> (-15.487109, -6.701871) centre (-6.894783, -14.42007) ccw
  arc A8 (-15.487109, -6.701871) -> (-15.035735, -7.66109) centre (0, 0) ccw
  arc A9 (-15.035735, -7.66109) -> (-12.104185, -7.158395) centre (-15.505755, 3.879177) ccw
  arc A10 (-12.104185, -7.158395) -> (-11.630821, -7.904298) centre (0, 0) ccw
  arc A11 (-11.630821, -7.904298) -> (-13.333866, -10.342807) centre (-3.092045, -15.6817) ccw
  arc A12 (-13.333866, -10.342807) -> (-12.658124, -11.159638) centre (0, 0) ccw
  arc A13 (-12.658124, -11.159638) -> (-9.943689, -9.943689) centre (-15.983325, -0.098819) ccw
  arc A14 (-9.943689, -9.943689) -> (-9.299698, -10.548437) centre (0, 0) ccw
  arc A15 (-9.299698, -10.548437) -> (-10.342807, -13.333866) centre (0.904978, -15.957991) ccw
  arc A16 (-10.342807, -13.333866) -> (-9.485157, -13.956985) centre (0, 0) ccw
  arc A17 (-9.485157, -13.956985) -> (-7.158395, -12.104185) centre (-15.456605, -4.070606) ccw
  arc A18 (-7.158395, -12.104185) -> (-6.384241, -12.529779) centre (0, 0) ccw
  arc A19 (-6.384241, -12.529779) -> (-6.701871, -15.487109) centre (4.845137, -15.231582) ccw
  arc A20 (-6.701871, -15.487109) -> (-5.716202, -15.877363) centre (0, 0) ccw
  arc A21 (-5.716202, -15.877363) -> (-3.923312, -13.50413) centre (-13.958688, -7.786621) ccw
  arc A22 (-3.923312, -13.50413) -> (-3.067639, -13.723829) centre (0, 0) ccw
  arc A23 (-3.067639, -13.723829) -> (-2.639832, -16.667241) centre (8.480859, -13.548118) ccw
  arc A24 (-2.639832, -16.667241) -> (-1.588078, -16.800108) centre (0, 0) ccw
  arc A25 (-1.588078, -16.800108) -> (-0.441714, -14.055561) centre (-11.583697, -11.013375) ccw
  arc A26 (-0.441714, -14.055561) -> (0.441714, -14.055561) centre (0, 0) ccw
  arc A27 (0.441714, -14.055561) -> (1.588078, -16.800108) centre (11.583697, -11.013375) ccw
  arc A28 (1.588078, -16.800108) -> (2.639832, -16.667241) centre (0, 0) ccw
  arc A29 (2.639832, -16.667241) -> (3.067639, -13.723829) centre (-8.480859, -13.548118) ccw
  arc A30 (3.067639, -13.723829) -> (3.923312, -13.50413) centre (0, 0) ccw
  arc A31 (3.923312, -13.50413) -> (5.716202, -15.877363) centre (13.958688, -7.786621) ccw
  arc A32 (5.716202, -15.877363) -> (6.701871, -15.487109) centre (0, 0) ccw
  arc A33 (6.701871, -15.487109) -> (6.384241, -12.529779) centre (-4.845137, -15.231582) ccw
  arc A34 (6.384241, -12.529779) -> (7.158395, -12.104185) centre (0, 0) ccw
  arc A35 (7.158395, -12.104185) -> (9.485157, -13.956985) centre (15.456605, -4.070606) ccw
  arc A36 (9.485157, -13.956985) -> (10.342807, -13.333866) centre (0, 0) ccw
  arc A37 (10.342807, -13.333866) -> (9.299698, -10.548437) centre (-0.904978, -15.957991) ccw
  arc A38 (9.299698, -10.548437) -> (9.943689, -9.943689) centre (0, 0) ccw
  arc A39 (9.943689, -9.943689) -> (12.658124, -11.159638) centre (15.983325, -0.098819) ccw
  arc A40 (12.658124, -11.159638) -> (13.333866, -10.342807) centre (0, 0) ccw
  arc A41 (13.333866, -10.342807) -> (11.630821, -7.904298) centre (3.092045, -15.6817) ccw
  arc A42 (11.630821, -7.904298) -> (12.104185, -7.158395) centre (0, 0) ccw
  arc A43 (12.104185, -7.158395) -> (15.035735, -7.66109) centre (15.505755, 3.879177) ccw
  arc A44 (15.035735, -7.66109) -> (15.487109, -6.701871) centre (0, 0) ccw
  arc A45 (15.487109, -6.701871) -> (13.231136, -4.763502) centre (6.894783, -14.42007) ccw
  arc A46 (13.231136, -4.763502) -> (13.50413, -3.923312) centre (0, 0) ccw
  arc A47 (13.50413, -3.923312) -> (16.468595, -3.681167) centre (14.053901, 7.61343) ccw
  arc A48 (16.468595, -3.681167) -> (16.667241, -2.639832) centre (0, 0) ccw
  arc A49 (16.667241, -2.639832) -> (14.00009, -1.323398) centre (10.264296, -12.252374) ccw
  arc A50 (17.618815, 2.579474) -> (14.00009, -1.323398) centre (34.4614, -16.665962) ccw
  line L2 (17.618815, 2.579474) -> (41.477523, 18.384068)
  arc A51 (41.477523, 18.384068) -> (34.515152, 28.894503) centre (36.452078, 22.61633) ccw
  line L3 (34.515152, 28.894503) -> (11.261601, 13.49078)
  arc A52 (6.506127, 12.466925) -> (11.261601, 13.49078) centre (7.785272, 18.081458) ccw
  line L4 (3.927111, 5.153676) -> (16.227464, 11.641901)
  arc A53 (18.454392, 8.280118) -> (16.227464, 11.641901) centre (15.058595, 8.449136) ccw
sketch "Szkic27" plane through (0, 0, 0) normal (0, 0, -1) x (-1, 0, 0)
  line L0 (-6.844874, -3.641782) -> (3.927111, 5.153676)
  arc A0 (-6.844874, -3.641782) -> (-4.617946, -7.003565) centre (-3.449077, -3.810801) ccw
  circle A1 centre (36.452078, 22.61633) radius 2
  arc A2 (6.506127, 12.466925) -> (-14.00009, -1.323398) centre (0, 0) ccw
  arc A3 (-14.00009, -1.323398) -> (-16.667241, -2.639832) centre (-10.264296, -12.252374) ccw
  arc A4 (-16.667241, -2.639832) -> (-16.468595, -3.681167) centre (0, 0) ccw
  arc A5 (-16.468595, -3.681167) -> (-13.50413, -3.923312) centre (-14.053901, 7.61343) ccw
  arc A6 (-13.50413, -3.923312) -> (-13.231136, -4.763502) centre (0, 0) ccw
  arc A7 (-13.231136, -4.763502) -> (-15.487109, -6.701871) centre (-6.894783, -14.42007) ccw
  arc A8 (-15.487109, -6.701871) -> (-15.035735, -7.66109) centre (0, 0) ccw
  arc A9 (-15.035735, -7.66109) -> (-12.104185, -7.158395) centre (-15.505755, 3.879177) ccw
  arc A10 (-12.104185, -7.158395) -> (-11.630821, -7.904298) centre (0, 0) ccw
  arc A11 (-11.630821, -7.904298) -> (-13.333866, -10.342807) centre (-3.092045, -15.6817) ccw
  arc A12 (-13.333866, -10.342807) -> (-12.658124, -11.159638) centre (0, 0) ccw
  arc A13 (-12.658124, -11.159638) -> (-9.943689, -9.943689) centre (-15.983325, -0.098819) ccw
  arc A14 (-9.943689, -9.943689) -> (-9.299698, -10.548437) centre (0, 0) ccw
  arc A15 (-9.299698, -10.548437) -> (-10.342807, -13.333866) centre (0.904978, -15.957991) ccw
  arc A16 (-10.342807, -13.333866) -> (-9.485157, -13.956985) centre (0, 0) ccw
  arc A17 (-9.485157, -13.956985) -> (-7.158395, -12.104185) centre (-15.456605, -4.070606) ccw
  arc A18 (-7.158395, -12.104185) -> (-6.384241, -12.529779) centre (0, 0) ccw
  arc A19 (-6.384241, -12.529779) -> (-6.701871, -15.487109) centre (4.845137, -15.231582) ccw
  arc A20 (-6.701871, -15.487109) -> (-5.716202, -15.877363) centre (0, 0) ccw
  arc A21 (-5.716202, -15.877363) -> (-3.923312, -13.50413) centre (-13.958688, -7.786621) ccw
  arc A22 (-3.923312, -13.50413) -> (-3.067639, -13.723829) centre (0, 0) ccw
  arc A23 (-3.067639, -13.723829) -> (-2.639832, -16.667241) centre (8.480859, -13.548118) ccw
  arc A24 (-2.639832, -16.667241) -> (-1.588078, -16.800108) centre (0, 0) ccw
  arc A25 (-1.588078, -16.800108) -> (-0.441714, -14.055561) centre (-11.583697, -11.013375) ccw
  arc A26 (-0.441714, -14.055561) -> (0.441714, -14.055561) centre (0, 0) ccw
  arc A27 (0.441714, -14.055561) -> (1.588078, -16.800108) centre (11.583697, -11.013375) ccw
  arc A28 (1.588078, -16.800108) -> (2.639832, -16.667241) centre (0, 0) ccw
  arc A29 (2.639832, -16.667241) -> (3.067639, -13.723829) centre (-8.480859, -13.548118) ccw
  arc A30 (3.067639, -13.723829) -> (3.923312, -13.50413) centre (0, 0) ccw
  arc A31 (3.923312, -13.50413) -> (5.716202, -15.877363) centre (13.958688, -7.786621) ccw
  arc A32 (5.716202, -15.877363) -> (6.701871, -15.487109) centre (0, 0) ccw
  arc A33 (6.701871, -15.487109) -> (6.384241, -12.529779) centre (-4.845137, -15.231582) ccw
  arc A34 (6.384241, -12.529779) -> (7.158395, -12.104185) centre (0, 0) ccw
  arc A35 (7.158395, -12.104185) -> (9.485157, -13.956985) centre (15.456605, -4.070606) ccw
  arc A36 (9.485157, -13.956985) -> (10.342807, -13.333866) centre (0, 0) ccw
  arc A37 (10.342807, -13.333866) -> (9.299698, -10.548437) centre (-0.904978, -15.957991) ccw
  arc A38 (9.299698, -10.548437) -> (9.943689, -9.943689) centre (0, 0) ccw
  arc A39 (9.943689, -9.943689) -> (12.658124, -11.159638) centre (15.983325, -0.098819) ccw
  arc A40 (12.658124, -11.159638) -> (13.333866, -10.342807) centre (0, 0) ccw
  arc A41 (13.333866, -10.342807) -> (11.630821, -7.904298) centre (3.092045, -15.6817) ccw
  arc A42 (11.630821, -7.904298) -> (12.104185, -7.158395) centre (0, 0) ccw
  arc A43 (12.104185, -7.158395) -> (15.035735, -7.66109) centre (15.505755, 3.879177) ccw
  arc A44 (15.035735, -7.66109) -> (15.487109, -6.701871) centre (0, 0) ccw
  arc A45 (15.487109, -6.701871) -> (13.231136, -4.763502) centre (6.894783, -14.42007) ccw
  arc A46 (13.231136, -4.763502) -> (13.50413, -3.923312) centre (0, 0) ccw
  arc A47 (13.50413, -3.923312) -> (16.468595, -3.681167) centre (14.053901, 7.61343) ccw
  arc A48 (16.468595, -3.681167) -> (16.667241, -2.639832) centre (0, 0) ccw
  arc A49 (16.667241, -2.639832) -> (14.00009, -1.323398) centre (10.264296, -12.252374) ccw
  arc A50 (17.618815, 2.579474) -> (14.00009, -1.323398) centre (34.4614, -16.665962) ccw
  line L1 (17.618815, 2.579474) -> (41.477523, 18.384068)
  arc A51 (41.477523, 18.384068) -> (34.515152, 28.894503) centre (36.452078, 22.61633) ccw
  line L2 (34.515152, 28.894503) -> (11.261601, 13.49078)
  arc A52 (6.506127, 12.466925) -> (11.261601, 13.49078) centre (7.785272, 18.081458) ccw
  line L3 (7.682407, -0.515341) -> (-4.617946, -7.003565)
  line L4 (18.454392, 8.280118) -> (7.682407, -0.515341)
  line L5 (3.927111, 5.153676) -> (16.227464, 11.641901)
  arc A53 (18.454392, 8.280118) -> (16.227464, 11.641901) centre (15.058595, 8.449136) ccw
  arc A54 (-6.844874, -3.641782) -> (-4.617946, -7.003565) centre (-3.449077, -3.810801) ccw
  arc A55 (18.454392, 8.280118) -> (16.227464, 11.641901) centre (15.058595, 8.449136) ccw
  line L6 (-1.586285, 3.007274) -> (1.586285, -3.007274)
  line L7 (-1.586285, 3.007274) -> (11.298868, 8.239622)
  line L8 (1.586285, -3.007274) -> (13.180338, 4.672738)
  arc A56 (13.180338, 4.672738) -> (11.298868, 8.239622) centre (9.818233, 5.178949) ccw
  line L9 (-1.586285, 3.007274) -> (-4.921024, 0.798311)
  line L10 (1.586285, -3.007274) -> (-2.119806, -4.512228)
  arc A57 (-4.921024, 0.798311) -> (-2.119806, -4.512228) centre (-1.268831, -0.669287) ccw
  dimension "d94" = 6.76625
  dimension "d95" = 6.8
  dimension "d96" = 6.8
  dimension "d98" = 84.29
  dimension "d99" = 13.90668
  dimension "d100" = 13.907
  dimension "d101" = 13.907
  dimension "d102" = 84.29
  dimension "d103" = 3.4
  dimension "d104" = 3.4
  dimension "d105" = 4
  dimension "d106" = 84.29
  dimension "d107" = 4
  dimension "d108" = 84.29
  dimension "d109" = 3.93603
  constraints: 10 end point, 8 point on circle, 4 centre point, 1 concentric, 1 midpoint, 1 perpendicular
  measures "d94" distance from line of L4.end L5
  measures "d95" distance of L6.start L6.end
  measures "d96" distance of L0.end L4.end
  measures "d98" angle of L7 L6
  measures "d99" distance of L0.end L5.end
  measures "d100" distance of L6.start L7.end
  measures "d101" distance of L6.end L8.end
  measures "d102" angle of L6 L8
  measures "d103" radius of A53
  measures "d104" radius of A56
  measures "d105" distance of L6.start L9.end
  measures "d106" angle of L6 L9
  measures "d107" distance of L6.end L10.end
  measures "d108" angle of L6 L10
  measures "d109" radius of A57
extrude "Wyciągnięcie proste18" cut sketch "Szkic27" against normal blind 3 contours A57 L9 L6 L0 | L0 L6 L10 A57 | L6 L7 L5 L0 | L0 L5 L7 A56 L8 L6
equation "\"d0\" = da_da"
equation "\"d1\" = da_b"
equation "\"d3\" = da_d"
equation "\"d16\" = da_aw"
equation "\"d43\" = da_aw"
equation "\"d46\" = da_aw"
equation "\"da_da\" = 33.75"
equation "\"da_b\" = 10"
equation "\"da_d\" = 31.25"
equation "\"da_aw\" = 109.375"
body "Solid1"
body "Srf1"
